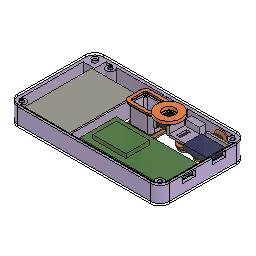
camera1_parametric (Autodesk Fusion 360 design; units mm, degrees)
part number: 2026-10-09-00-26-43-538
part number: 2026-10-09-00-32-59-840
part number: 2026-10-09-00-35-13-257
part number: 2026-10-09-00-35-15-477
part number: 2026-10-09-00-35-17-517
part number: 2026-10-09-00-35-17-942
part number: 2026-10-09-00-35-19-892
part number: 2026-10-09-00-35-22-447
part number: 2026-10-09-00-35-24-029
Autodesk Fusion 360 part; units mm, degrees
(part 1 of 2)
sketch "Outline sketch" plane through (0, 0, 0) normal (0, 0, 1) x (1, 0, 0) in component "Frame"
  line L0 (0, 0) -> (116, 0)
  line L1 (116, 0) -> (116, 66)
  line L2 (116, 66) -> (0, 66)
  line L3 (0, 66) -> (0, 0)
  dimension "d73" = 116
  dimension "d74" = 66
  constraint coincident L0.start L3.end
  measures "d73" horizontal distance of L0.start L0.end
  measures "d74" vertical distance of L0.start L2.end
extrude "Outline" add sketch "Outline sketch" along normal blind 12 from surface at 1.6 makes body 1 in component "Frame"
fillet "Outer corners" radius 7 4 edges at (0, 66, 7.6) (116, 66, 7.6) (116, 0, 7.6) (0, 0, 7.6) on bodies 1 in component "Frame"
sketch "Inner pocket sketch" plane through (0, 0, 0) normal (0, 0, 1) x (1, 0, 0) in component "Frame"
  line L0 (2.2, 2.2) -> (113.8, 2.2)
  line L1 (113.8, 2.2) -> (113.8, 63.8)
  line L2 (113.8, 63.8) -> (2.2, 63.8)
  line L3 (2.2, 63.8) -> (2.2, 2.2)
  dimension "d80" = 111.6
  dimension "d81" = 61.6
  dimension "d82" = 2.2
  dimension "d83" = 2.2
  measures "d80" horizontal distance of L0.start L0.end
  measures "d81" vertical distance of L0.start L2.end
  measures "d82" horizontal distance of origin L0.start
  measures "d83" vertical distance of origin L0.start
extrude "Inner pocket" cut sketch "Inner pocket sketch" along normal blind 14 from surface at 0.6 bodies 1 in component "Frame"
fillet "Inner corners" radius 4.8 4 edges at (113.8, 2.2, 7.6) (2.2, 2.2, 7.6) (2.2, 63.8, 7.6) (113.8, 63.8, 7.6) on bodies 1 in component "Frame"
sketch "Screw posts sketch" plane through (0, 0, 0) normal (0, 0, 1) x (1, 0, 0) in component "Frame"
  circle A0 centre (5, 5) radius 3.2
  circle A1 centre (111, 5) radius 3.2
  circle A2 centre (111, 61) radius 3.2
  circle A3 centre (17, 61) radius 3.2
  dimension "d89" = 6.4
  dimension "d90" = 5
  dimension "d91" = 5
  dimension "d92" = 6.4
  dimension "d93" = 111
  dimension "d94" = 6.4
  dimension "d95" = 61
  dimension "d96" = 6.4
  dimension "d97" = 17
  constraint horizontal A0.centre A1.centre
  constraint vertical A1.centre A2.centre
  constraint horizontal A2.centre A3.centre
  measures "d89" diameter of A0
  measures "d90" horizontal distance of origin A0.centre
  measures "d91" vertical distance of origin A0.centre
  measures "d92" diameter of A1
  measures "d93" horizontal distance of origin A1.centre
  measures "d94" diameter of A2
  measures "d95" vertical distance of origin A2.centre
  measures "d96" diameter of A3
  measures "d97" horizontal distance of origin A3.centre
extrude "Screw posts" add sketch "Screw posts sketch" along normal blind 12 from surface at 1.6 bodies 1 in component "Frame"
sketch "Keychain corner sketch" plane through (0, 0, 0) normal (0, 0, 1) x (1, 0, 0) in component "Frame"
  line L0 (2.2, 55) -> (11, 55)
  line L1 (11, 55) -> (11, 63.8)
  line L2 (11, 63.8) -> (2.2, 63.8)
  line L3 (2.2, 63.8) -> (2.2, 55)
  dimension "d101" = 8.8
  dimension "d102" = 8.8
  dimension "d103" = 2.2
  dimension "d104" = 55
  measures "d101" horizontal distance of L0.start L0.end
  measures "d102" vertical distance of L0.start L2.end
  measures "d103" horizontal distance of origin L0.start
  measures "d104" vertical distance of origin L0.start
extrude "Keychain corner" add sketch "Keychain corner sketch" along normal blind 12 from surface at 1.6 bodies 1 in component "Frame"
sketch "Viewfinder tube sketch" plane through (0, 0, 0) normal (0, 0, 1) x (1, 0, 0) in component "Frame"
  line L0 (46.8, 43.8) -> (65.2, 43.8)
  line L1 (65.2, 43.8) -> (65.2, 58.2)
  line L2 (65.2, 58.2) -> (46.8, 58.2)
  line L3 (46.8, 58.2) -> (46.8, 43.8)
  dimension "d108" = 18.4
  dimension "d109" = 14.4
  dimension "d110" = 46.8
  dimension "d111" = 43.8
  measures "d108" horizontal distance of L0.start L0.end
  measures "d109" vertical distance of L0.start L2.end
  measures "d110" horizontal distance of origin L0.start
  measures "d111" vertical distance of origin L0.start
extrude "Viewfinder tube" add sketch "Viewfinder tube sketch" along normal blind 12 from surface at 1.6 separate body makes body 2 in component "Frame"
sketch "Viewfinder rib sketch" plane through (0, 0, 0) normal (0, 0, 1) x (1, 0, 0) in component "Frame"
  line L0 (55, 57) -> (57, 57)
  line L1 (57, 57) -> (57, 64.3)
  line L2 (57, 64.3) -> (55, 64.3)
  line L3 (55, 64.3) -> (55, 57)
  dimension "d115" = 2
  dimension "d116" = 7.3
  dimension "d117" = 55
  dimension "d118" = 57
  measures "d115" horizontal distance of L0.start L0.end
  measures "d116" vertical distance of L0.start L2.end
  measures "d117" horizontal distance of origin L0.start
  measures "d118" vertical distance of origin L0.start
extrude "Viewfinder rib" add sketch "Viewfinder rib sketch" along normal blind 12 from surface at 1.6 bodies 1 2 in component "Frame"
sketch "Camera cradle sketch" plane through (0, 0, 0) normal (0, 0, 1) x (1, 0, 0) in component "Frame"
  line L0 (66.15, 45.15) -> (77.85, 45.15)
  line L1 (77.85, 45.15) -> (77.85, 56.85)
  line L2 (77.85, 56.85) -> (66.15, 56.85)
  line L3 (66.15, 56.85) -> (66.15, 45.15)
  dimension "d122" = 11.7
  dimension "d123" = 11.7
  dimension "d124" = 66.15
  dimension "d125" = 45.15
  measures "d122" horizontal distance of L0.start L0.end
  measures "d123" vertical distance of L0.start L2.end
  measures "d124" horizontal distance of origin L0.start
  measures "d125" vertical distance of origin L0.start
extrude "Camera cradle" add sketch "Camera cradle sketch" along normal blind 6.7 from surface at 6.9 separate body makes body 3 in component "Frame"
sketch "Camera cradle rib sketch" plane through (0, 0, 0) normal (0, 0, 1) x (1, 0, 0) in component "Frame"
  line L0 (70.5, 55.25) -> (73.5, 55.25)
  line L1 (73.5, 55.25) -> (73.5, 64.3)
  line L2 (73.5, 64.3) -> (70.5, 64.3)
  line L3 (70.5, 64.3) -> (70.5, 55.25)
  dimension "d129" = 3
  dimension "d130" = 9.05
  dimension "d131" = 70.5
  dimension "d132" = 55.25
  measures "d129" horizontal distance of L0.start L0.end
  measures "d130" vertical distance of L0.start L2.end
  measures "d131" horizontal distance of origin L0.start
  measures "d132" vertical distance of origin L0.start
extrude "Camera cradle rib" add sketch "Camera cradle rib sketch" along normal blind 6.7 from surface at 6.9 bodies 1 3 in component "Frame"
sketch "Button shelf sketch" plane through (0, 0, 0) normal (0, 0, 1) x (1, 0, 0) in component "Frame"
  line L0 (79, 44) -> (114.3, 44)
  line L1 (114.3, 44) -> (114.3, 56)
  line L2 (114.3, 56) -> (79, 56)
  line L3 (79, 56) -> (79, 44)
  dimension "d136" = 35.3
  dimension "d137" = 12
  dimension "d138" = 79
  dimension "d139" = 44
  measures "d136" horizontal distance of L0.start L0.end
  measures "d137" vertical distance of L0.start L2.end
  measures "d138" horizontal distance of origin L0.start
  measures "d139" vertical distance of origin L0.start
extrude "Button shelf" add sketch "Button shelf sketch" along normal blind 1.6 from surface at 7.6 bodies 1 in component "Frame"
sketch "Shutter ledge sketch" plane through (0, 0, 0) normal (0, 0, 1) x (1, 0, 0) in component "Frame"
  line L0 (95, 56.2) -> (114.3, 56.2)
  line L1 (114.3, 56.2) -> (114.3, 57.8)
  line L2 (114.3, 57.8) -> (95, 57.8)
  line L3 (95, 57.8) -> (95, 56.2)
  dimension "d143" = 19.3
  dimension "d144" = 1.6
  dimension "d145" = 95
  dimension "d146" = 56.2
  measures "d143" horizontal distance of L0.start L0.end
  measures "d144" vertical distance of L0.start L2.end
  measures "d145" horizontal distance of origin L0.start
  measures "d146" vertical distance of origin L0.start
extrude "Shutter ledge" add sketch "Shutter ledge sketch" along normal blind 10 from surface at 2.6 bodies 1 in component "Frame"
sketch "Power switch housing sketch" plane through (0, 0, 0) normal (0, 0, 1) x (1, 0, 0) in component "Frame"
  line L0 (76.5, 59) -> (87.5, 59)
  line L1 (87.5, 59) -> (87.5, 64.3)
  line L2 (87.5, 64.3) -> (76.5, 64.3)
  line L3 (76.5, 64.3) -> (76.5, 59)
  dimension "d150" = 11
  dimension "d151" = 5.3
  dimension "d152" = 76.5
  dimension "d153" = 59
  measures "d150" horizontal distance of L0.start L0.end
  measures "d151" vertical distance of L0.start L2.end
  measures "d152" horizontal distance of origin L0.start
  measures "d153" vertical distance of origin L0.start
extrude "Power switch housing" add sketch "Power switch housing sketch" along normal blind 6 from surface at 4.6 bodies 1 in component "Frame"
sketch "Insert holes back sketch" plane through (0, 0, 0) normal (0, 0, 1) x (1, 0, 0) in component "Frame"
  circle A0 centre (5, 5) radius 1.6
  circle A1 centre (111, 5) radius 1.6
  circle A2 centre (111, 61) radius 1.6
  circle A3 centre (17, 61) radius 1.6
  dimension "d167" = 3.2
  dimension "d168" = 5
  dimension "d169" = 5
  dimension "d170" = 3.2
  dimension "d171" = 111
  dimension "d172" = 3.2
  dimension "d173" = 61
  dimension "d174" = 3.2
  dimension "d175" = 17
  constraint horizontal A0.centre A1.centre
  constraint vertical A1.centre A2.centre
  constraint horizontal A2.centre A3.centre
  measures "d167" diameter of A0
  measures "d168" horizontal distance of origin A0.centre
  measures "d169" vertical distance of origin A0.centre
  measures "d170" diameter of A1
  measures "d171" horizontal distance of origin A1.centre
  measures "d172" diameter of A2
  measures "d173" vertical distance of origin A2.centre
  measures "d174" diameter of A3
  measures "d175" horizontal distance of origin A3.centre
extrude "Insert holes back" cut sketch "Insert holes back sketch" along normal blind 4.5 from surface at 0.6 bodies 1 in component "Frame"
sketch "Insert holes front sketch" plane through (0, 0, 0) normal (0, 0, 1) x (1, 0, 0) in component "Frame"
  circle A0 centre (5, 5) radius 1.6
  circle A1 centre (111, 5) radius 1.6
  circle A2 centre (111, 61) radius 1.6
  circle A3 centre (17, 61) radius 1.6
  dimension "d179" = 3.2
  dimension "d180" = 5
  dimension "d181" = 5
  dimension "d182" = 3.2
  dimension "d183" = 111
  dimension "d184" = 3.2
  dimension "d185" = 61
  dimension "d186" = 3.2
  dimension "d187" = 17
  constraint horizontal A0.centre A1.centre
  constraint vertical A1.centre A2.centre
  constraint horizontal A2.centre A3.centre
  measures "d179" diameter of A0
  measures "d180" horizontal distance of origin A0.centre
  measures "d181" vertical distance of origin A0.centre
  measures "d182" diameter of A1
  measures "d183" horizontal distance of origin A1.centre
  measures "d184" diameter of A2
  measures "d185" vertical distance of origin A2.centre
  measures "d186" diameter of A3
  measures "d187" horizontal distance of origin A3.centre
extrude "Insert holes front" cut sketch "Insert holes front sketch" along normal blind 4.5 from surface at 10.1 bodies 1 in component "Frame"
sketch "Post pilot holes sketch" plane through (0, 0, 0) normal (0, 0, 1) x (1, 0, 0) in component "Frame"
  circle A0 centre (5, 5) radius 0.9
  circle A1 centre (111, 5) radius 0.9
  circle A2 centre (111, 61) radius 0.9
  circle A3 centre (17, 61) radius 0.9
  dimension "d191" = 1.8
  dimension "d192" = 5
  dimension "d193" = 5
  dimension "d194" = 1.8
  dimension "d195" = 111
  dimension "d196" = 1.8
  dimension "d197" = 61
  dimension "d198" = 1.8
  dimension "d199" = 17
  constraint horizontal A0.centre A1.centre
  constraint vertical A1.centre A2.centre
  constraint horizontal A2.centre A3.centre
  measures "d191" diameter of A0
  measures "d192" horizontal distance of origin A0.centre
  measures "d193" vertical distance of origin A0.centre
  measures "d194" diameter of A1
  measures "d195" horizontal distance of origin A1.centre
  measures "d196" diameter of A2
  measures "d197" vertical distance of origin A2.centre
  measures "d198" diameter of A3
  measures "d199" horizontal distance of origin A3.centre
extrude "Post pilot holes" cut sketch "Post pilot holes sketch" along normal blind 14 from surface at 0.6 bodies 1 in component "Frame"
sketch "Keychain hole sketch" plane through (0, 0, 0) normal (0, 0, 1) x (1, 0, 0) in component "Frame"
  circle A0 centre (6, 60) radius 2.1
  dimension "d203" = 4.2
  dimension "d204" = 6
  dimension "d205" = 60
  measures "d203" diameter of A0
  measures "d204" horizontal distance of origin A0.centre
  measures "d205" vertical distance of origin A0.centre
extrude "Keychain hole" cut sketch "Keychain hole sketch" along normal blind 14 from surface at 0.6 bodies 1 in component "Frame"
sketch "Viewfinder window sketch" plane through (0, 0, 0) normal (0, 0, 1) x (1, 0, 0) in component "Frame"
  line L0 (48, 45) -> (64, 45)
  line L1 (64, 45) -> (64, 57)
  line L2 (64, 57) -> (48, 57)
  line L3 (48, 57) -> (48, 45)
  dimension "d209" = 16
  dimension "d210" = 12
  dimension "d211" = 48
  dimension "d212" = 45
  measures "d209" horizontal distance of L0.start L0.end
  measures "d210" vertical distance of L0.start L2.end
  measures "d211" horizontal distance of origin L0.start
  measures "d212" vertical distance of origin L0.start
extrude "Viewfinder window" cut sketch "Viewfinder window sketch" along normal blind 14 from surface at 0.6 bodies 1 in component "Frame"
sketch "Camera pocket sketch" plane through (0, 0, 0) normal (0, 0, 1) x (1, 0, 0) in component "Frame"
  line L0 (67.45, 46.45) -> (76.55, 46.45)
  line L1 (76.55, 46.45) -> (76.55, 55.55)
  line L2 (76.55, 55.55) -> (67.45, 55.55)
  line L3 (67.45, 55.55) -> (67.45, 46.45)
  dimension "d216" = 9.1
  dimension "d217" = 9.1
  dimension "d218" = 67.45
  dimension "d219" = 46.45
  measures "d216" horizontal distance of L0.start L0.end
  measures "d217" vertical distance of L0.start L2.end
  measures "d218" horizontal distance of origin L0.start
  measures "d219" vertical distance of origin L0.start
extrude "Camera pocket" cut sketch "Camera pocket sketch" along normal blind 6.8 from surface at 7.8 bodies 1 in component "Frame"
sketch "Camera flex slot sketch" plane through (0, 0, 0) normal (0, 0, 1) x (1, 0, 0) in component "Frame"
  line L0 (68, 44.75) -> (76, 44.75)
  line L1 (76, 44.75) -> (76, 47.75)
  line L2 (76, 47.75) -> (68, 47.75)
  line L3 (68, 47.75) -> (68, 44.75)
  dimension "d223" = 8
  dimension "d224" = 3
  dimension "d225" = 68
  dimension "d226" = 44.75
  measures "d223" horizontal distance of L0.start L0.end
  measures "d224" vertical distance of L0.start L2.end
  measures "d225" horizontal distance of origin L0.start
  measures "d226" vertical distance of origin L0.start
extrude "Camera flex slot" cut sketch "Camera flex slot sketch" along normal blind 8.5 from surface at 6.1 bodies 1 in component "Frame"
sketch "Button pockets sketch" plane through (0, 0, 0) normal (0, 0, 1) x (1, 0, 0) in component "Frame"
  line L0 (80.7, 46.7) -> (87.3, 46.7)
  line L1 (87.3, 46.7) -> (87.3, 53.3)
  line L2 (87.3, 53.3) -> (80.7, 53.3)
  line L3 (80.7, 53.3) -> (80.7, 46.7)
  line L4 (92.7, 46.7) -> (99.3, 46.7)
  line L5 (99.3, 46.7) -> (99.3, 53.3)
  line L6 (99.3, 53.3) -> (92.7, 53.3)
  line L7 (92.7, 53.3) -> (92.7, 46.7)
  line L8 (104.7, 46.7) -> (111.3, 46.7)
  line L9 (111.3, 46.7) -> (111.3, 53.3)
  line L10 (111.3, 53.3) -> (104.7, 53.3)
  line L11 (104.7, 53.3) -> (104.7, 46.7)
  dimension "d230" = 6.6
  dimension "d231" = 6.6
  dimension "d232" = 80.7
  dimension "d233" = 46.7
  dimension "d234" = 6.6
  dimension "d235" = 6.6
  dimension "d236" = 92.7
  dimension "d237" = 6.6
  dimension "d238" = 6.6
  dimension "d239" = 104.7
  constraint horizontal L0.start L4.start
  constraint horizontal L0.start L8.start
  measures "d230" horizontal distance of L0.start L0.end
  measures "d231" vertical distance of L0.start L2.end
  measures "d232" horizontal distance of origin L0.start
  measures "d233" vertical distance of origin L0.start
  measures "d234" horizontal distance of L4.start L4.end
  measures "d235" vertical distance of L4.start L6.end
  measures "d236" horizontal distance of origin L4.start
  measures "d237" horizontal distance of L8.start L8.end
  measures "d238" vertical distance of L8.start L10.end
  measures "d239" horizontal distance of origin L8.start
extrude "Button pockets" cut sketch "Button pockets sketch" along normal blind 3.51 from surface at 4.1 bodies 1 in component "Frame"
sketch "Button leg slots sketch" plane through (0, 0, 0) normal (0, 0, 1) x (1, 0, 0) in component "Frame"
  line L0 (82.5, 46.2) -> (85.5, 46.2)
  line L1 (85.5, 46.2) -> (85.5, 53.8)
  line L2 (85.5, 53.8) -> (82.5, 53.8)
  line L3 (82.5, 53.8) -> (82.5, 46.2)
  line L4 (94.5, 46.2) -> (97.5, 46.2)
  line L5 (97.5, 46.2) -> (97.5, 53.8)
  line L6 (97.5, 53.8) -> (94.5, 53.8)
  line L7 (94.5, 53.8) -> (94.5, 46.2)
  line L8 (106.5, 46.2) -> (109.5, 46.2)
  line L9 (109.5, 46.2) -> (109.5, 53.8)
  line L10 (109.5, 53.8) -> (106.5, 53.8)
  line L11 (106.5, 53.8) -> (106.5, 46.2)
  dimension "d243" = 3
  dimension "d244" = 7.6
  dimension "d245" = 82.5
  dimension "d246" = 46.2
  dimension "d247" = 3
  dimension "d248" = 7.6
  dimension "d249" = 94.5
  dimension "d250" = 3
  dimension "d251" = 7.6
  dimension "d252" = 106.5
  constraint horizontal L0.start L4.start
  constraint horizontal L0.start L8.start
  measures "d243" horizontal distance of L0.start L0.end
  measures "d244" vertical distance of L0.start L2.end
  measures "d245" horizontal distance of origin L0.start
  measures "d246" vertical distance of origin L0.start
  measures "d247" horizontal distance of L4.start L4.end
  measures "d248" vertical distance of L4.start L6.end
  measures "d249" horizontal distance of origin L4.start
  measures "d250" horizontal distance of L8.start L8.end
  measures "d251" vertical distance of L8.start L10.end
  measures "d252" horizontal distance of origin L8.start
extrude "Button leg slots" cut sketch "Button leg slots sketch" along normal blind 1.8 from surface at 7.5 bodies 1 in component "Frame"
sketch "Power switch pocket sketch" plane through (0, 0, 0) normal (0, 0, 1) x (1, 0, 0) in component "Frame"
  line L0 (77.4, 59.9) -> (86.6, 59.9)
  line L1 (86.6, 59.9) -> (86.6, 63.81)
  line L2 (86.6, 63.81) -> (77.4, 63.81)
  line L3 (77.4, 63.81) -> (77.4, 59.9)
  dimension "d256" = 9.2
  dimension "d257" = 3.91
  dimension "d258" = 77.4
  dimension "d259" = 59.9
  measures "d256" horizontal distance of L0.start L0.end
  measures "d257" vertical distance of L0.start L2.end
  measures "d258" horizontal distance of origin L0.start
  measures "d259" vertical distance of origin L0.start
extrude "Power switch pocket" cut sketch "Power switch pocket sketch" along normal blind 4.2 from surface at 5.5 bodies 1 in component "Frame"
sketch "Power switch knob slot sketch" plane through (0, 0, 0) normal (0, 0, 1) x (1, 0, 0) in component "Frame"
  line L0 (79.7, 63.3) -> (84.3, 63.3)
  line L1 (84.3, 63.3) -> (84.3, 66.5)
  line L2 (84.3, 66.5) -> (79.7, 66.5)
  line L3 (79.7, 66.5) -> (79.7, 63.3)
  dimension "d263" = 4.6
  dimension "d264" = 3.2
  dimension "d265" = 79.7
  dimension "d266" = 63.3
  measures "d263" horizontal distance of L0.start L0.end
  measures "d264" vertical distance of L0.start L2.end
  measures "d265" horizontal distance of origin L0.start
  measures "d266" vertical distance of origin L0.start
extrude "Power switch knob slot" cut sketch "Power switch knob slot sketch" along normal blind 2.1 from surface at 6.55 bodies 1 in component "Frame"
sketch "Power switch finger recess sketch" plane through (0, 0, 0) normal (0, 0, 1) x (1, 0, 0) in component "Frame"
  line L0 (76, 64.8) -> (88, 64.8)
  line L1 (88, 64.8) -> (88, 66.8)
  line L2 (88, 66.8) -> (76, 66.8)
  line L3 (76, 66.8) -> (76, 64.8)
  dimension "d270" = 12
  dimension "d271" = 2
  dimension "d272" = 76
  dimension "d273" = 64.8
  measures "d270" horizontal distance of L0.start L0.end
  measures "d271" vertical distance of L0.start L2.end
  measures "d272" horizontal distance of origin L0.start
  measures "d273" vertical distance of origin L0.start
extrude "Power switch finger recess" cut sketch "Power switch finger recess sketch" along normal blind 7 from surface at 4.1 bodies 1 in component "Frame"
sketch "Charge port sketch" plane through (0, 0, 0) normal (0, 0, 1) x (1, 0, 0) in component "Frame"
  line L0 (112.8, 40.5) -> (117, 40.5)
  line L1 (117, 40.5) -> (117, 50.5)
  line L2 (117, 50.5) -> (112.8, 50.5)
  line L3 (112.8, 50.5) -> (112.8, 40.5)
  dimension "d277" = 4.2
  dimension "d278" = 10
  dimension "d279" = 112.8
  dimension "d280" = 40.5
  measures "d277" horizontal distance of L0.start L0.end
  measures "d278" vertical distance of L0.start L2.end
  measures "d279" horizontal distance of origin L0.start
  measures "d280" vertical distance of origin L0.start
extrude "Charge port" cut sketch "Charge port sketch" along normal blind 4.4 from surface at 9.4 bodies 1 in component "Frame"
sketch "Board USB port sketch" plane through (0, 0, 0) normal (0, 0, 1) x (1, 0, 0) in component "Frame"
  line L0 (112.8, 17) -> (117, 17)
  line L1 (117, 17) -> (117, 27)
  line L2 (117, 27) -> (112.8, 27)
  line L3 (112.8, 27) -> (112.8, 17)
  dimension "d284" = 4.2
  dimension "d285" = 10
  dimension "d286" = 112.8
  dimension "d287" = 17
  measures "d284" horizontal distance of L0.start L0.end
  measures "d285" vertical distance of L0.start L2.end
  measures "d286" horizontal distance of origin L0.start
  measures "d287" vertical distance of origin L0.start
extrude "Board USB port" cut sketch "Board USB port sketch" along normal blind 4.4 from surface at 8.2 bodies 1 in component "Frame"
ref_plane "WorkPlane1" through (0, 62.8, 0) normal (0, 1, 0) x (0, 0, 1) in component "Frame"
sketch "Shutter hole sketch" plane through (0, 62.8, 0) normal (0, 1, 0) x (1, 0, 0) in component "Frame"
  circle A0 centre (100, -7.6) radius 4.2
  dimension "d293" = 8.4
  dimension "d294" = 100
  dimension "d295" = 7.6
  measures "d293" diameter of A0
  measures "d294" horizontal distance of origin A0.centre
  measures "d295" vertical distance of origin A0.centre
extrude "Shutter hole" cut sketch "Shutter hole sketch" along normal blind 4.2 bodies 1 in component "Frame"
fillet "Viewfinder window corners" radius 1.6 4 edges at (48, 45, 7.6) (64, 45, 7.6) (64, 57, 7.6) (48, 57, 7.6) on bodies 1 in component "Frame"
fillet "Viewfinder tube corners" radius 2.8 2 edges at (65.2, 43.8, 7.6) (46.8, 43.8, 7.6) on bodies 1 in component "Frame"
sketch "Outline sketch (2)" plane through (0, 0, 0) normal (0, 0, 1) x (1, 0, 0) in component "Back plate (clear)"
  line L0 (0, 0) -> (116, 0)
  line L1 (116, 0) -> (116, 66)
  line L2 (116, 66) -> (0, 66)
  line L3 (0, 66) -> (0, 0)
  dimension "d308" = 116
  dimension "d309" = 66
  constraint coincident L0.start L3.end
  measures "d308" horizontal distance of L0.start L0.end
  measures "d309" vertical distance of L0.start L2.end
extrude "Outline'" add sketch "Outline sketch (2)" along normal blind 1.6 separate body makes body 4 in component "Back plate (clear)"
fillet "Corners" radius 7 4 edges at (0, 66, 0.8) (116, 66, 0.8) (116, 0, 0.8) (0, 0, 0.8) on bodies 4 in component "Back plate (clear)"
sketch "Screw holes sketch" plane through (0, 0, 0) normal (0, 0, 1) x (1, 0, 0) in component "Back plate (clear)"
  circle A0 centre (5, 5) radius 1.2
  circle A1 centre (111, 5) radius 1.2
  circle A2 centre (111, 61) radius 1.2
  circle A3 centre (17, 61) radius 1.2
  dimension "d315" = 2.4
  dimension "d316" = 5
  dimension "d317" = 5
  dimension "d318" = 2.4
  dimension "d319" = 111
  dimension "d320" = 2.4
  dimension "d321" = 61
  dimension "d322" = 2.4
  dimension "d323" = 17
  constraint horizontal A0.centre A1.centre
  constraint vertical A1.centre A2.centre
  constraint horizontal A2.centre A3.centre
  measures "d315" diameter of A0
  measures "d316" horizontal distance of origin A0.centre
  measures "d317" vertical distance of origin A0.centre
  measures "d318" diameter of A1
  measures "d319" horizontal distance of origin A1.centre
  measures "d320" diameter of A2
  measures "d321" vertical distance of origin A2.centre
  measures "d322" diameter of A3
  measures "d323" horizontal distance of origin A3.centre
extrude "Screw holes" cut sketch "Screw holes sketch" along normal blind 3.6 from surface at -1 bodies 4 in component "Back plate (clear)"
sketch "Keychain hole sketch (2)" plane through (0, 0, 0) normal (0, 0, 1) x (1, 0, 0) in component "Back plate (clear)"
  circle A0 centre (6, 60) radius 2.1
  dimension "d327" = 4.2
  dimension "d328" = 6
  dimension "d329" = 60
  measures "d327" diameter of A0
  measures "d328" horizontal distance of origin A0.centre
  measures "d329" vertical distance of origin A0.centre
extrude "Keychain hole'" cut sketch "Keychain hole sketch (2)" along normal blind 3.6 from surface at -1 bodies 4 in component "Back plate (clear)"
sketch "Viewfinder window sketch (2)" plane through (0, 0, 0) normal (0, 0, 1) x (1, 0, 0) in component "Back plate (clear)"
  line L0 (48, 45) -> (64, 45)
  line L1 (64, 45) -> (64, 57)
  line L2 (64, 57) -> (48, 57)
  line L3 (48, 57) -> (48, 45)
  dimension "d333" = 16
  dimension "d334" = 12
  dimension "d335" = 48
  dimension "d336" = 45
  measures "d333" horizontal distance of L0.start L0.end
  measures "d334" vertical distance of L0.start L2.end
  measures "d335" horizontal distance of origin L0.start
  measures "d336" vertical distance of origin L0.start
extrude "Viewfinder window (1)" cut sketch "Viewfinder window sketch (2)" along normal blind 3.6 from surface at -1 bodies 1 in component "Frame"
extrude "Extrude4" cut sketch "Viewfinder window sketch (2)" along normal blind 3.6 from surface at -1 bodies 4 in component "Back plate (clear)"
fillet "Viewfinder window corners'" radius 1.6 4 edges at (64, 45, 0.8) (48, 45, 0.8) (48, 57, 0.8) (64, 57, 0.8) on bodies 4 in component "Back plate (clear)"
sketch "Screen window sketch" plane through (0, 0, 0) normal (0, 0, 1) x (1, 0, 0) in component "Back plate (clear)"
  line L0 (57.5, 4.9) -> (98.9, 4.9)
  line L1 (98.9, 4.9) -> (98.9, 36.1)
  line L2 (98.9, 36.1) -> (57.5, 36.1)
  line L3 (57.5, 36.1) -> (57.5, 4.9)
  dimension "d345" = 41.4
  dimension "d346" = 31.2
  dimension "d347" = 57.5
  dimension "d348" = 4.9
  measures "d345" horizontal distance of L0.start L0.end
  measures "d346" vertical distance of L0.start L2.end
  measures "d347" horizontal distance of origin L0.start
  measures "d348" vertical distance of origin L0.start
extrude "Screen window" cut sketch "Screen window sketch" along normal blind 3.6 from surface at -1 bodies 4 in component "Back plate (clear)"
sketch "Button holes sketch" plane through (0, 0, 0) normal (0, 0, 1) x (1, 0, 0) in component "Back plate (clear)"
  circle A0 centre (84, 50) radius 3.2
  circle A1 centre (96, 50) radius 3.2
  circle A2 centre (108, 50) radius 3.2
  dimension "d352" = 6.4
  dimension "d353" = 84
  dimension "d354" = 50
  dimension "d355" = 6.4
  dimension "d356" = 96
  dimension "d357" = 6.4
  dimension "d358" = 108
  constraint horizontal A0.centre A1.centre
  constraint horizontal A0.centre A2.centre
  measures "d352" diameter of A0
  measures "d353" horizontal distance of origin A0.centre
  measures "d354" vertical distance of origin A0.centre
  measures "d355" diameter of A1
  measures "d356" horizontal distance of origin A1.centre
  measures "d357" diameter of A2
  measures "d358" horizontal distance of origin A2.centre
extrude "Button holes" cut sketch "Button holes sketch" along normal blind 3.6 from surface at -1 bodies 4 in component "Back plate (clear)"
sketch "Outline sketch (3)" plane through (0, 0, 0) normal (0, 0, 1) x (1, 0, 0) in component "Front plate (clear)"
  line L0 (0, 0) -> (116, 0)
  line L1 (116, 0) -> (116, 66)
  line L2 (116, 66) -> (0, 66)
  line L3 (0, 66) -> (0, 0)
  dimension "d362" = 116
  dimension "d363" = 66
  constraint coincident L0.start L3.end
  measures "d362" horizontal distance of L0.start L0.end
  measures "d363" vertical distance of L0.start L2.end
extrude "Outline''" add sketch "Outline sketch (3)" along normal blind 1.6 from surface at 13.6 separate body makes body 5 in component "Front plate (clear)"
fillet "Corners'" radius 7 4 edges at (0, 66, 14.4) (116, 66, 14.4) (116, 0, 14.4) (0, 0, 14.4) on bodies 5 in component "Front plate (clear)"
sketch "Screw holes sketch (2)" plane through (0, 0, 0) normal (0, 0, 1) x (1, 0, 0) in component "Front plate (clear)"
  circle A0 centre (5, 5) radius 1.2
  circle A1 centre (111, 5) radius 1.2
  circle A2 centre (111, 61) radius 1.2
  circle A3 centre (17, 61) radius 1.2
  dimension "d369" = 2.4
  dimension "d370" = 5
  dimension "d371" = 5
  dimension "d372" = 2.4
  dimension "d373" = 111
  dimension "d374" = 2.4
  dimension "d375" = 61
  dimension "d376" = 2.4
  dimension "d377" = 17
  constraint horizontal A0.centre A1.centre
  constraint vertical A1.centre A2.centre
  constraint horizontal A2.centre A3.centre
  measures "d369" diameter of A0
  measures "d370" horizontal distance of origin A0.centre
  measures "d371" vertical distance of origin A0.centre
  measures "d372" diameter of A1
  measures "d373" horizontal distance of origin A1.centre
  measures "d374" diameter of A2
  measures "d375" vertical distance of origin A2.centre
  measures "d376" diameter of A3
  measures "d377" horizontal distance of origin A3.centre
extrude "Screw holes'" cut sketch "Screw holes sketch (2)" along normal blind 3.6 from surface at 12.6 bodies 5 in component "Front plate (clear)"
sketch "Keychain hole sketch (3)" plane through (0, 0, 0) normal (0, 0, 1) x (1, 0, 0) in component "Front plate (clear)"
  circle A0 centre (6, 60) radius 2.1
  dimension "d381" = 4.2
  dimension "d382" = 6
  dimension "d383" = 60
  measures "d381" diameter of A0
  measures "d382" horizontal distance of origin A0.centre
  measures "d383" vertical distance of origin A0.centre
extrude "Keychain hole''" cut sketch "Keychain hole sketch (3)" along normal blind 3.6 from surface at 12.6 bodies 5 in component "Front plate (clear)"
sketch "Viewfinder window sketch (3)" plane through (0, 0, 0) normal (0, 0, 1) x (1, 0, 0) in component "Front plate (clear)"
  line L0 (48, 45) -> (64, 45)
  line L1 (64, 45) -> (64, 57)
  line L2 (64, 57) -> (48, 57)
  line L3 (48, 57) -> (48, 45)
  dimension "d387" = 16
  dimension "d388" = 12
  dimension "d389" = 48
  dimension "d390" = 45
  measures "d387" horizontal distance of L0.start L0.end
  measures "d388" vertical distance of L0.start L2.end
  measures "d389" horizontal distance of origin L0.start
  measures "d390" vertical distance of origin L0.start
extrude "Viewfinder window (2)" cut sketch "Viewfinder window sketch (3)" along normal blind 3.6 from surface at 12.6 bodies 1 in component "Frame"
extrude "Extrude4'" cut sketch "Viewfinder window sketch (3)" along normal blind 3.6 from surface at 12.6 bodies 5 in component "Front plate (clear)"
fillet "Viewfinder window corners''" radius 1.6 4 edges at (64, 45, 14.4) (48, 45, 14.4) (48, 57, 14.4) (64, 57, 14.4) on bodies 5 in component "Front plate (clear)"
sketch "Lens hole sketch" plane through (0, 0, 0) normal (0, 0, 1) x (1, 0, 0) in component "Front plate (clear)"
  circle A0 centre (72, 51) radius 4.4
  dimension "d399" = 8.8
  dimension "d400" = 72
  dimension "d401" = 51
  measures "d399" diameter of A0
  measures "d400" horizontal distance of origin A0.centre
  measures "d401" vertical distance of origin A0.centre
extrude "Lens hole" cut sketch "Lens hole sketch" along normal blind 3.6 from surface at 12.6 bodies 5 in component "Front plate (clear)"
sketch "Lens ring sketch" plane through (0, 0, 0) normal (0, 0, 1) x (1, 0, 0) in component "Lens ring"
  circle A0 centre (72, 51) radius 9.5
  circle A1 centre (72, 51) radius 4.6
  dimension "d405" = 19
  dimension "d406" = 72
  dimension "d407" = 51
  dimension "d408" = 9.2
  constraint vertical A0.centre A1.centre
  constraint horizontal A0.centre A1.centre
  measures "d405" diameter of A0
  measures "d406" horizontal distance of origin A0.centre
  measures "d407" vertical distance of origin A0.centre
  measures "d408" diameter of A1
extrude "Lens ring" add sketch "Lens ring sketch" along normal blind 2.4 from surface at 15.2 separate body makes body 6 in component "Lens ring"
sketch "Trim front sketch" plane through (0, 0, 0) normal (0, 0, 1) x (1, 0, 0) in component "Viewfinder trims"
  line L0 (45.6, 42.6) -> (66.4, 42.6)
  line L1 (66.4, 42.6) -> (66.4, 59.4)
  line L2 (66.4, 59.4) -> (45.6, 59.4)
  line L3 (45.6, 59.4) -> (45.6, 42.6)
  line L4 (48, 45) -> (64, 45)
  line L5 (64, 45) -> (64, 57)
  line L6 (64, 57) -> (48, 57)
  line L7 (48, 57) -> (48, 45)
  dimension "d412" = 20.8
  dimension "d413" = 16.8
  dimension "d414" = 45.6
  dimension "d415" = 42.6
  dimension "d416" = 16
  dimension "d417" = 12
  dimension "d418" = 48
  dimension "d419" = 45
  measures "d412" horizontal distance of L0.start L0.end
  measures "d413" vertical distance of L0.start L2.end
  measures "d414" horizontal distance of origin L0.start
  measures "d415" vertical distance of origin L0.start
  measures "d416" horizontal distance of L4.start L4.end
  measures "d417" vertical distance of L4.start L6.end
  measures "d418" horizontal distance of origin L4.start
  measures "d419" vertical distance of origin L4.start
extrude "Trim front" add sketch "Trim front sketch" along normal blind 1.2 from surface at 15.2 separate body makes body 7 in component "Viewfinder trims"
fillet "Trim front outer corners" radius 4 4 edges at (45.6, 59.4, 15.8) (66.4, 59.4, 15.8) (66.4, 42.6, 15.8) (45.6, 42.6, 15.8) on bodies 7 in component "Viewfinder trims"
fillet "Trim front inner corners" radius 1.6 4 edges at (48, 45, 15.8) (64, 45, 15.8) (64, 57, 15.8) (48, 57, 15.8) on bodies 7 in component "Viewfinder trims"
sketch "Trim back sketch" plane through (0, 0, 0) normal (0, 0, 1) x (1, 0, 0) in component "Viewfinder trims"
  line L0 (45.6, 42.6) -> (66.4, 42.6)
  line L1 (66.4, 42.6) -> (66.4, 59.4)
  line L2 (66.4, 59.4) -> (45.6, 59.4)
  line L3 (45.6, 59.4) -> (45.6, 42.6)
  line L4 (48, 45) -> (64, 45)
  line L5 (64, 45) -> (64, 57)
  line L6 (64, 57) -> (48, 57)
  line L7 (48, 57) -> (48, 45)
  dimension "d427" = 20.8
  dimension "d428" = 16.8
  dimension "d429" = 45.6
  dimension "d430" = 42.6
  dimension "d431" = 16
  dimension "d432" = 12
  dimension "d433" = 48
  dimension "d434" = 45
  measures "d427" horizontal distance of L0.start L0.end
  measures "d428" vertical distance of L0.start L2.end
  measures "d429" horizontal distance of origin L0.start
  measures "d430" vertical distance of origin L0.start
  measures "d431" horizontal distance of L4.start L4.end
  measures "d432" vertical distance of L4.start L6.end
  measures "d433" horizontal distance of origin L4.start
  measures "d434" vertical distance of origin L4.start
extrude "Trim back" add sketch "Trim back sketch" along normal blind 1.2 from surface at -1.2 separate body makes body 8 in component "Viewfinder trims"
fillet "Trim back outer corners" radius 4 4 edges at (45.6, 59.4, -0.6) (66.4, 59.4, -0.6) (66.4, 42.6, -0.6) (45.6, 42.6, -0.6) on bodies 8 in component "Viewfinder trims"
fillet "Trim back inner corners" radius 1.6 4 edges at (48, 45, -0.6) (64, 45, -0.6) (64, 57, -0.6) (48, 57, -0.6) on bodies 8 in component "Viewfinder trims"
sketch "Cap prev shaft sketch" plane through (0, 0, 0) normal (0, 0, 1) x (1, 0, 0) in component "Button caps"
  circle A0 centre (84, 50) radius 3
  dimension "d442" = 6
  dimension "d443" = 84
  dimension "d444" = 50
  measures "d442" diameter of A0
  measures "d443" horizontal distance of origin A0.centre
  measures "d444" vertical distance of origin A0.centre
extrude "Cap prev shaft" add sketch "Cap prev shaft sketch" along normal blind 2.8 from surface at -1.2 separate body makes body 9 in component "Button caps"
sketch "Cap prev flange sketch" plane through (0, 0, 0) normal (0, 0, 1) x (1, 0, 0) in component "Button caps"
  circle A0 centre (84, 50) radius 4.2
  dimension "d448" = 8.4
  dimension "d449" = 84
  dimension "d450" = 50
  measures "d448" diameter of A0
  measures "d449" horizontal distance of origin A0.centre
  measures "d450" vertical distance of origin A0.centre
extrude "Cap prev flange" add sketch "Cap prev flange sketch" along normal blind 1 from surface at 1.6 bodies 9 in component "Button caps"
sketch "Cap ok shaft sketch" plane through (0, 0, 0) normal (0, 0, 1) x (1, 0, 0) in component "Button caps"
  circle A0 centre (96, 50) radius 3
  dimension "d454" = 6
  dimension "d455" = 96
  dimension "d456" = 50
  measures "d454" diameter of A0
  measures "d455" horizontal distance of origin A0.centre
  measures "d456" vertical distance of origin A0.centre
extrude "Cap ok shaft" add sketch "Cap ok shaft sketch" along normal blind 2.8 from surface at -1.2 separate body makes body 10 in component "Button caps"
sketch "Cap ok flange sketch" plane through (0, 0, 0) normal (0, 0, 1) x (1, 0, 0) in component "Button caps"
  circle A0 centre (96, 50) radius 4.2
  dimension "d460" = 8.4
  dimension "d461" = 96
  dimension "d462" = 50
  measures "d460" diameter of A0
  measures "d461" horizontal distance of origin A0.centre
  measures "d462" vertical distance of origin A0.centre
extrude "Cap ok flange" add sketch "Cap ok flange sketch" along normal blind 1 from surface at 1.6 bodies 10 in component "Button caps"
sketch "Cap next shaft sketch" plane through (0, 0, 0) normal (0, 0, 1) x (1, 0, 0) in component "Button caps"
  circle A0 centre (108, 50) radius 3
  dimension "d466" = 6
  dimension "d467" = 108
  dimension "d468" = 50
  measures "d466" diameter of A0
  measures "d467" horizontal distance of origin A0.centre
  measures "d468" vertical distance of origin A0.centre
extrude "Cap next shaft" add sketch "Cap next shaft sketch" along normal blind 2.8 from surface at -1.2 separate body makes body 11 in component "Button caps"
sketch "Cap next flange sketch" plane through (0, 0, 0) normal (0, 0, 1) x (1, 0, 0) in component "Button caps"
  circle A0 centre (108, 50) radius 4.2
  dimension "d472" = 8.4
  dimension "d473" = 108
  dimension "d474" = 50
  measures "d472" diameter of A0
  measures "d473" horizontal distance of origin A0.centre
  measures "d474" vertical distance of origin A0.centre
extrude "Cap next flange" add sketch "Cap next flange sketch" along normal blind 1 from surface at 1.6 bodies 11 in component "Button caps"
ref_plane "WorkPlane1" through (0, 62.8, 0) normal (0, 1, 0) x (0, 0, 1) in component "Shutter cap"
sketch "Shutter flange sketch" plane through (0, 62.8, 0) normal (0, 1, 0) x (1, 0, 0) in component "Shutter cap"
  circle A0 centre (100, -7.6) radius 5.2
  dimension "d480" = 10.4
  dimension "d481" = 100
  dimension "d482" = 7.6
  measures "d480" diameter of A0
  measures "d481" horizontal distance of origin A0.centre
  measures "d482" vertical distance of origin A0.centre
extrude "Shutter flange" add sketch "Shutter flange sketch" along normal blind 1 separate body makes body 12 in component "Shutter cap"
ref_plane "WorkPlane2" through (0, 63.8, 0) normal (0, 1, 0) x (0, 0, 1) in component "Shutter cap"
sketch "Shutter shaft sketch" plane through (0, 63.8, 0) normal (0, 1, 0) x (1, 0, 0) in component "Shutter cap"
  circle A0 centre (100, -7.6) radius 4
  dimension "d487" = 8
  dimension "d488" = 100
  dimension "d489" = 7.6
  measures "d487" diameter of A0
  measures "d488" horizontal distance of origin A0.centre
  measures "d489" vertical distance of origin A0.centre
extrude "Shutter shaft" add sketch "Shutter shaft sketch" along normal blind 3.2 bodies 12 in component "Shutter cap"
fillet "Domed top" radius 2 1 edges at (96.2707, 67, 9.0465) on bodies 12 in component "Shutter cap"
sketch "Battery 103450 2000mAh sketch" plane through (0, 0, 0) normal (0, 0, 1) x (1, 0, 0) in component "Reference electronics (not printed)"
  line L0 (9, 2.6) -> (44, 2.6)
  line L1 (44, 2.6) -> (44, 54.6)
  line L2 (44, 54.6) -> (9, 54.6)
  line L3 (9, 54.6) -> (9, 2.6)
  dimension "d494" = 35
  dimension "d495" = 52
  dimension "d496" = 9
  dimension "d497" = 2.6
  measures "d494" horizontal distance of L0.start L0.end
  measures "d495" vertical distance of L0.start L2.end
  measures "d496" horizontal distance of origin L0.start
  measures "d497" vertical distance of origin L0.start
extrude "Battery 103450 2000mAh" add sketch "Battery 103450 2000mAh sketch" along normal blind 10.5 from surface at 2.35 separate body makes body 13 in component "Reference electronics (not printed)"
sketch "GOOUUU ESP32-S3-CAM board sketch" plane through (0, 0, 0) normal (0, 0, 1) x (1, 0, 0) in component "Reference electronics (not printed)"
  line L0 (46, 8.5) -> (113, 8.5)
  line L1 (113, 8.5) -> (113, 36.5)
  line L2 (113, 36.5) -> (46, 36.5)
  line L3 (46, 36.5) -> (46, 8.5)
  dimension "d501" = 67
  dimension "d502" = 28
  dimension "d503" = 46
  dimension "d504" = 8.5
  measures "d501" horizontal distance of L0.start L0.end
  measures "d502" vertical distance of L0.start L2.end
  measures "d503" horizontal distance of origin L0.start
  measures "d504" vertical distance of origin L0.start
extrude "GOOUUU ESP32-S3-CAM board" add sketch "GOOUUU ESP32-S3-CAM board sketch" along normal blind 1.6 from surface at 6.6 separate body makes body 14 in component "Reference electronics (not printed)"
sketch "ESP32-S3 module sketch" plane through (0, 0, 0) normal (0, 0, 1) x (1, 0, 0) in component "Reference electronics (not printed)"
  line L0 (52, 12.5) -> (77.5, 12.5)
  line L1 (77.5, 12.5) -> (77.5, 30.5)
  line L2 (77.5, 30.5) -> (52, 30.5)
  line L3 (52, 30.5) -> (52, 12.5)
  dimension "d508" = 25.5
  dimension "d509" = 18
  dimension "d510" = 52
  dimension "d511" = 12.5
  measures "d508" horizontal distance of L0.start L0.end
  measures "d509" vertical distance of L0.start L2.end
  measures "d510" horizontal distance of origin L0.start
  measures "d511" vertical distance of origin L0.start
extrude "ESP32-S3 module" add sketch "ESP32-S3 module sketch" along normal blind 3.1 from surface at 8.2 bodies 14 in component "Reference electronics (not printed)"
sketch "Screen module 2.0in sketch" plane through (0, 0, 0) normal (0, 0, 1) x (1, 0, 0) in component "Reference electronics (not printed)"
  line L0 (49.2, 3) -> (107.2, 3)
  line L1 (107.2, 3) -> (107.2, 38)
  line L2 (107.2, 38) -> (49.2, 38)
  line L3 (49.2, 38) -> (49.2, 3)
  dimension "d515" = 58
  dimension "d516" = 35
  dimension "d517" = 49.2
  dimension "d518" = 3
  measures "d515" horizontal distance of L0.start L0.end
  measures "d516" vertical distance of L0.start L2.end
  measures "d517" horizontal distance of origin L0.start
  measures "d518" vertical distance of origin L0.start
extrude "Screen module 2.0in" add sketch "Screen module 2.0in sketch" along normal blind 4.5 from surface at 1.6 separate body makes body 15 in component "Reference electronics (not printed)"
sketch "Screen active area sketch" plane through (0, 0, 0) normal (0, 0, 1) x (1, 0, 0) in component "Reference electronics (not printed)"
  line L0 (57.8, 5.2) -> (98.6, 5.2)
  line L1 (98.6, 5.2) -> (98.6, 35.8)
  line L2 (98.6, 35.8) -> (57.8, 35.8)
  line L3 (57.8, 35.8) -> (57.8, 5.2)
  dimension "d522" = 40.8
  dimension "d523" = 30.6
  dimension "d524" = 57.8
  dimension "d525" = 5.2
  measures "d522" horizontal distance of L0.start L0.end
  measures "d523" vertical distance of L0.start L2.end
  measures "d524" horizontal distance of origin L0.start
  measures "d525" vertical distance of origin L0.start
extrude "Screen active area" add sketch "Screen active area sketch" along normal blind 0.2 from surface at 1.4 separate body makes body 16 in component "Reference electronics (not printed)"
sketch "Charge-boost module sketch" plane through (0, 0, 0) normal (0, 0, 1) x (1, 0, 0) in component "Reference electronics (not printed)"
  line L0 (95.5, 38.5) -> (113.5, 38.5)
  line L1 (113.5, 38.5) -> (113.5, 52.5)
  line L2 (113.5, 52.5) -> (95.5, 52.5)
  line L3 (95.5, 52.5) -> (95.5, 38.5)
  dimension "d529" = 18
  dimension "d530" = 14
  dimension "d531" = 95.5
  dimension "d532" = 38.5
  measures "d529" horizontal distance of L0.start L0.end
  measures "d530" vertical distance of L0.start L2.end
  measures "d531" horizontal distance of origin L0.start
  measures "d532" vertical distance of origin L0.start
extrude "Charge-boost module" add sketch "Charge-boost module sketch" along normal blind 4 from surface at 9.6 separate body makes body 17 in component "Reference electronics (not printed)"
sketch "OV3660 camera module sketch" plane through (0, 0, 0) normal (0, 0, 1) x (1, 0, 0) in component "Reference electronics (not printed)"
  line L0 (67.75, 46.75) -> (76.25, 46.75)
  line L1 (76.25, 46.75) -> (76.25, 55.25)
  line L2 (76.25, 55.25) -> (67.75, 55.25)
  line L3 (67.75, 55.25) -> (67.75, 46.75)
  dimension "d536" = 8.5
  dimension "d537" = 8.5
  dimension "d538" = 67.75
  dimension "d539" = 46.75
  measures "d536" horizontal distance of L0.start L0.end
  measures "d537" vertical distance of L0.start L2.end
  measures "d538" horizontal distance of origin L0.start
  measures "d539" vertical distance of origin L0.start
extrude "OV3660 camera module" add sketch "OV3660 camera module sketch" along normal blind 2.5 from surface at 8.1 separate body makes body 18 in component "Reference electronics (not printed)"
sketch "Lens barrel sketch" plane through (0, 0, 0) normal (0, 0, 1) x (1, 0, 0) in component "Reference electronics (not printed)"
  circle A0 centre (72, 51) radius 4
  dimension "d543" = 8
  dimension "d544" = 72
  dimension "d545" = 51
  measures "d543" diameter of A0
  measures "d544" horizontal distance of origin A0.centre
  measures "d545" vertical distance of origin A0.centre
extrude "Lens barrel" add sketch "Lens barrel sketch" along normal blind 5.5 from surface at 8.1 bodies 18 in component "Reference electronics (not printed)"
sketch "Button switch prev sketch" plane through (0, 0, 0) normal (0, 0, 1) x (1, 0, 0) in component "Reference electronics (not printed)"
  line L0 (81, 47) -> (87, 47)
  line L1 (87, 47) -> (87, 53)
  line L2 (87, 53) -> (81, 53)
  line L3 (81, 53) -> (81, 47)
  dimension "d549" = 6
  dimension "d550" = 6
  dimension "d551" = 81
  dimension "d552" = 47
  measures "d549" horizontal distance of L0.start L0.end
  measures "d550" vertical distance of L0.start L2.end
  measures "d551" horizontal distance of origin L0.start
  measures "d552" vertical distance of origin L0.start
extrude "Button switch prev" add sketch "Button switch prev sketch" along normal blind 3.5 from surface at 4.1 separate body makes body 19 in component "Reference electronics (not printed)"
sketch "Button switch ok sketch" plane through (0, 0, 0) normal (0, 0, 1) x (1, 0, 0) in component "Reference electronics (not printed)"
  line L0 (93, 47) -> (99, 47)
  line L1 (99, 47) -> (99, 53)
  line L2 (99, 53) -> (93, 53)
  line L3 (93, 53) -> (93, 47)
  dimension "d556" = 6
  dimension "d557" = 6
  dimension "d558" = 93
  dimension "d559" = 47
  measures "d556" horizontal distance of L0.start L0.end
  measures "d557" vertical distance of L0.start L2.end
  measures "d558" horizontal distance of origin L0.start
  measures "d559" vertical distance of origin L0.start
extrude "Button switch ok" add sketch "Button switch ok sketch" along normal blind 3.5 from surface at 4.1 separate body makes body 20 in component "Reference electronics (not printed)"
sketch "Button switch next sketch" plane through (0, 0, 0) normal (0, 0, 1) x (1, 0, 0) in component "Reference electronics (not printed)"
  line L0 (105, 47) -> (111, 47)
  line L1 (111, 47) -> (111, 53)
  line L2 (111, 53) -> (105, 53)
  line L3 (105, 53) -> (105, 47)
  dimension "d563" = 6
  dimension "d564" = 6
  dimension "d565" = 105
  dimension "d566" = 47
  measures "d563" horizontal distance of L0.start L0.end
  measures "d564" vertical distance of L0.start L2.end
  measures "d565" horizontal distance of origin L0.start
  measures "d566" vertical distance of origin L0.start
extrude "Button switch next" add sketch "Button switch next sketch" along normal blind 3.5 from surface at 4.1 separate body makes body 21 in component "Reference electronics (not printed)"
sketch "Shutter switch sketch" plane through (0, 0, 0) normal (0, 0, 1) x (1, 0, 0) in component "Reference electronics (not printed)"
  line L0 (97, 57.8) -> (103, 57.8)
  line L1 (103, 57.8) -> (103, 61.3)
  line L2 (103, 61.3) -> (97, 61.3)
  line L3 (97, 61.3) -> (97, 57.8)
  dimension "d570" = 6
  dimension "d571" = 3.5
  dimension "d572" = 97
  dimension "d573" = 57.8
  measures "d570" horizontal distance of L0.start L0.end
  measures "d571" vertical distance of L0.start L2.end
  measures "d572" horizontal distance of origin L0.start
  measures "d573" vertical distance of origin L0.start
extrude "Shutter switch" add sketch "Shutter switch sketch" along normal blind 6 from surface at 4.6 separate body makes body 22 in component "Reference electronics (not printed)"